BSIDESFrame (Autodesk Fusion 360 design; units mm, degrees)
Autodesk Fusion 360 part; units mm, degrees
sketch "Sketch1" plane through (0, 0, 0) normal (0, 1, 0) x (1, 0, 0)
  circle A0 centre (5.406183, 7.424795) radius 1.6
  line L0 (5.406183, 7.424795) -> (42.106183, 7.424795) construction
  circle A1 centre (42.106183, 7.424795) radius 1.6
  circle A2 centre (5.406183, 7.424795) radius 3.25
  circle A3 centre (42.106183, 7.424795) radius 3.25
  line L1 (5.406183, 7.424795) -> (5.406183, 4.174795) construction
  line L2 (42.106183, 7.424795) -> (42.106183, 4.174795) construction
  line L3 (5.406183, 7.424795) -> (5.406183, 10.674795) construction
  line L4 (42.106183, 7.424795) -> (42.106183, 10.674795) construction
  line L5 (5.406183, 10.674795) -> (42.106183, 10.674795)
  line L6 (5.406183, 4.174795) -> (42.106183, 4.174795)
  constraint horizontal L0
  constraint concentric A1 A3
  constraint perpendicular L0 L2
  constraint perpendicular L0 L3
  constraint perpendicular L0 L4
  constraint tangent A3 L5
  constraint tangent A2 L6
  constraint perpendicular L1 L6
extrude "Extrude1" add sketch "Sketch1" along normal blind 11 contours A2 | A2 A3 L5 L6 | A3 picked at (2.831926, 8.218848) picked at (28.795575, 7.424795) picked at (40.131385, 5.592449)
sketch "Sketch2" plane through (0, 0, -4.174795) normal (0, 0, 1) x (1, 0, 0)
  line L0 (5.406183, 0) -> (42.106183, 0)
  line L1 (42.106183, 0) -> (42.106183, 11)
  line L2 (42.106183, 11) -> (5.406183, 11)
  line L3 (5.406183, 11) -> (5.406183, 0)
  circle A0 centre (37.206183, 4.5) radius 2.6
  dimension "d12" = 5.2
  measures "d12" diameter of A0
extrude "Extrude2" cut sketch "Sketch2" against normal blind 6.5 contours A0 picked at (38.034347, 4.244546)
sketch "Sketch3" plane through (0, 11, 0) normal (0, 1, 0) x (-1, 0, 0)
  circle A0 centre (-42.106183, -7.424795) radius 1.6
  circle A1 centre (-5.406183, -7.424795) radius 1.6
  arc A2 (-5.406183, -10.674795) -> (-5.406183, -4.174795) centre (-5.406183, -7.424795) ccw
  line L0 (-5.406183, -4.174795) -> (-42.106183, -4.174795)
  arc A3 (-42.106183, -4.174795) -> (-42.106183, -10.674795) centre (-42.106183, -7.424795) ccw
  line L1 (-42.106183, -10.674795) -> (-5.406183, -10.674795)
  point P0 (-40.606183, -4.174795)
  point P1 (-40.506183, -7.424795)
sketch "Sketch4" plane through (0, 0, -4.174795) normal (0, 0, 1) x (1, 0, 0)
  circle A0 centre (37.206183, 4.5) radius 2.6
  line L0 (5.406183, 0) -> (42.106183, 0)
  line L1 (42.106183, 0) -> (42.106183, 11)
  line L2 (42.106183, 11) -> (5.406183, 11)
  line L3 (5.406183, 11) -> (5.406183, 0)
  line L4 (34.606183, 4.5) -> (34.606183, 0)
  line L5 (39.806183, 4.5) -> (39.806183, 0)
  point P0 (34.606183, 4.5)
  constraint tangent A0 L4
  constraint perpendicular L0 L4
  constraint perpendicular L0 L5
  constraint tangent A0 L5
extrude "Extrude3" add sketch "Sketch4" along normal blind 8 contours A0 L0 L4 L5 picked at (37.141417, 0.635757)
sketch "Sketch5" plane through (0, 0, 0) normal (0, -1, 0) x (1, 0, 0)
  circle A0 centre (42.106183, -7.424795) radius 1.6
  circle A1 centre (5.406183, -7.424795) radius 1.6
  arc A2 (5.406183, -4.174795) -> (5.406183, -10.674795) centre (5.406183, -7.424795) ccw
  line L0 (5.406183, -10.674795) -> (42.106183, -10.674795)
  arc A3 (42.106183, -10.674795) -> (42.106183, -4.174795) centre (42.106183, -7.424795) ccw
  line L1 (42.106183, -4.174795) -> (39.806183, -4.174795)
  line L2 (39.806183, -4.174795) -> (39.806183, 3.825205)
  line L3 (39.806183, 3.825205) -> (34.606183, 3.825205)
  line L4 (34.606183, 3.825205) -> (34.606183, -4.174795)
  line L5 (34.606183, -4.174795) -> (5.406183, -4.174795)
  line L6 (34.606183, -4.174795) -> (39.806183, -4.174795)
  line L7 (37.206183, -4.174795) -> (37.206183, 3.125205)
  circle A4 centre (37.206183, 3.125205) radius 0.5
  dimension "d17" = 7.3
  dimension "d18" = 1
  constraint perpendicular L6 L7
  measures "d18" diameter of A4
ref_plane "WorkPlane1" through (37.21175, 1.900006, 3.113719) normal (-0.002141, 0.999998, 0) x (-0.999998, -0.002141, 0)
sketch "Sketch6" plane through (37.213891, 1.900011, 3.113719) normal (-0.002141, 0.999998, 0) x (-0.999998, -0.002141, 0)
  circle A0 centre (0, 0) radius 0.511903
  constraint coincident A0.centre origin
sphere "SpherePrimitive1" cut diameter 0.9 placed x (-0.99999771, -0.00214102, 0) y (0, 0, 1) z (-0.00214102, 0.99999771, 0) at (37.213891, 1.900011, 3.113719)
fillet "Fillet1" radius 0.2 2 edges at (37.662085, 1.940283, 3.113719) (36.765466, 1.937625, 3.113719)
sketch "Sketch8" plane through (0, 0, 3.825205) normal (0, 0, 1) x (1, 0, 0)
  line L0 (34.606183, 4.5) -> (34.606183, 0)
  line L1 (34.606183, 0) -> (39.806183, 0)
  line L2 (39.806183, 0) -> (39.806183, 4.5)
  arc A0 (34.606183, 4.5) -> (39.806183, 4.5) centre (37.206183, 4.5) ccw
  line L3 (34.606183, 3.401952) -> (39.806183, 3.401952)
  constraint horizontal L3
extrude "Extrude4" cut sketch "Sketch8" against normal blind 8 contours L0 A0 L3 | L2 A0 L3 picked at (34.723621, 3.519583) picked at (39.688746, 3.519583)
sketch "Sketch9" plane through (0, 0, -4.174795) normal (0, 0, 1) x (1, 0, 0)
  line L0 (34.606183, 0) -> (34.606183, 3.401952)
  line L1 (34.606183, 3.401952) -> (34.849429, 3.401952)
  arc A0 (39.562937, 3.401952) -> (34.849429, 3.401952) centre (37.206183, 4.5) ccw
  line L2 (39.562937, 3.401952) -> (39.806183, 3.401952)
  line L3 (39.806183, 3.401952) -> (39.806183, 0)
  line L4 (39.806183, 0) -> (42.106183, 0)
  line L5 (42.106183, 0) -> (42.106183, 11)
  line L6 (42.106183, 11) -> (5.406183, 11)
  line L7 (5.406183, 11) -> (5.406183, 0)
  line L8 (5.406183, 0) -> (34.606183, 0)
  line L9 (37.213891, 1.900011) -> (37.214399, 9.150011)
  line L10 (37.214399, 9.150011) -> (42.106183, 9.150011)
  line L11 (42.106183, 0) -> (42.106183, 9.150011)
  line L12 (39.806183, 0) -> (42.106183, 0)
  line L13 (39.806183, 0) -> (39.806183, 9.150011)
  line L14 (37.214399, 9.150011) -> (37.214399, 11)
  line L15 (42.106183, 9.150011) -> (42.106183, 11)
  line L16 (37.214399, 11) -> (42.106183, 11)
  point P0 (37.213891, 1.900011)
  dimension "d25" = 7.25
  constraint perpendicular L5 L10
  constraint perpendicular L10 L13
  constraint vertical L14
extrude "Extrude5" add sketch "Sketch9" along normal blind 8 contours L5 L6 L10 L14 L15 L16 | L3 L4 L5 L10 L11 L12 L13 picked at (39.708922, 10.383337) picked at (41.339517, 4.550004)
fillet "Fillet2" radius 0.25 1 edges at (39.806183, 9.150011, -0.174795)
fillet "Fillet3" radius 2.5 1 edges at (39.806183, 3.401952, -0.174795)
sketch "Sketch10" plane through (0, 0, 3.825205) normal (0, 0, 1) x (1, 0, 0)
  line L0 (37.214399, 9.150011) -> (39.556183, 9.150011)
  arc A0 (39.806183, 8.900011) -> (39.556183, 9.150011) centre (39.556183, 8.900011) ccw
  line L1 (39.806183, 8.900011) -> (39.806183, 4.477619)
  arc A1 (39.562937, 3.401952) -> (39.806183, 4.477619) centre (37.306183, 4.477619) ccw
  arc A2 (34.849429, 3.401952) -> (39.562937, 3.401952) centre (37.206183, 4.5) ccw
  line L2 (34.849429, 3.401952) -> (34.606183, 3.401952)
  line L3 (34.606183, 3.401952) -> (34.606183, 0)
  line L4 (34.606183, 0) -> (42.106183, 0)
  line L5 (42.106183, 0) -> (42.106183, 11)
  line L6 (42.106183, 11) -> (37.214399, 11)
  line L7 (37.214399, 11) -> (37.214399, 9.150011)
  line L8 (37.213891, 1.900011) -> (34.606183, 1.900011)
  point P0 (37.213891, 1.900011)
  constraint horizontal L8
extrude "Extrude6" cut sketch "Sketch10" against normal blind 8 contours A2 L2 L3 L8 picked at (34.747076, 2.793651)
sketch "Sketch11" plane through (0, 0, 3.825205) normal (0, 0, 1) x (1, 0, 0)
  line L0 (37.201733, 1.900011) -> (34.606183, 1.900011)
  line L1 (34.606183, 1.900011) -> (34.606183, 0)
  line L2 (34.606183, 0) -> (42.106183, 0)
  line L3 (42.106183, 0) -> (42.106183, 11)
  line L4 (42.106183, 11) -> (37.214399, 11)
  line L5 (37.214399, 11) -> (37.214399, 9.150011)
  line L6 (37.214399, 9.150011) -> (39.556183, 9.150011)
  arc A0 (39.806183, 8.900011) -> (39.556183, 9.150011) centre (39.556183, 8.900011) ccw
  line L7 (39.806183, 8.900011) -> (39.806183, 4.477619)
  arc A1 (39.562937, 3.401952) -> (39.806183, 4.477619) centre (37.306183, 4.477619) ccw
  arc A2 (37.201733, 1.900004) -> (39.562937, 3.401952) centre (37.206183, 4.5) ccw
  line L8 (35.903958, 1.900011) -> (35.903958, 0)
  constraint vertical L8
extrude "Extrude7" cut sketch "Sketch11" against normal blind 8 contours L0 L1 L2 L8 picked at (35.471367, 0.633337)
fillet "Fillet5" radius 1 2 edges at (37.214399, 9.150011, -0.174795) (37.214399, 11, -0.174795)
fillet "Fillet6" radius 1 1 edges at (35.903958, 1.900011, -0.174795)
sketch "Sketch12" plane through (0, 11, 0) normal (0, 1, 0) x (-1, 0, 0)
  line L0 (-38.203083, -4.174795) -> (-38.203083, 3.825205)
  line L1 (-38.203083, 3.825205) -> (-42.106183, 3.825205)
  line L2 (-42.106183, 3.825205) -> (-42.106183, -4.174795)
  arc A0 (-42.106183, -4.174795) -> (-42.106183, -10.674795) centre (-42.106183, -7.424795) ccw
  line L3 (-42.106183, -10.674795) -> (-5.406183, -10.674795)
  arc A1 (-5.406183, -10.674795) -> (-5.406183, -4.174795) centre (-5.406183, -7.424795) ccw
  line L4 (-5.406183, -4.174795) -> (-38.203083, -4.174795)
  circle A2 centre (-42.106183, -7.424795) radius 1.6
  circle A3 centre (-5.406183, -7.424795) radius 1.6
  line L5 (-45.313167, -6.89777) -> (-42.106183, 3.825205)
extrude "Extrude8" add sketch "Sketch12" against normal blind 11 contours L2 A0 L5 picked at (-42.261706, -1.51935)
